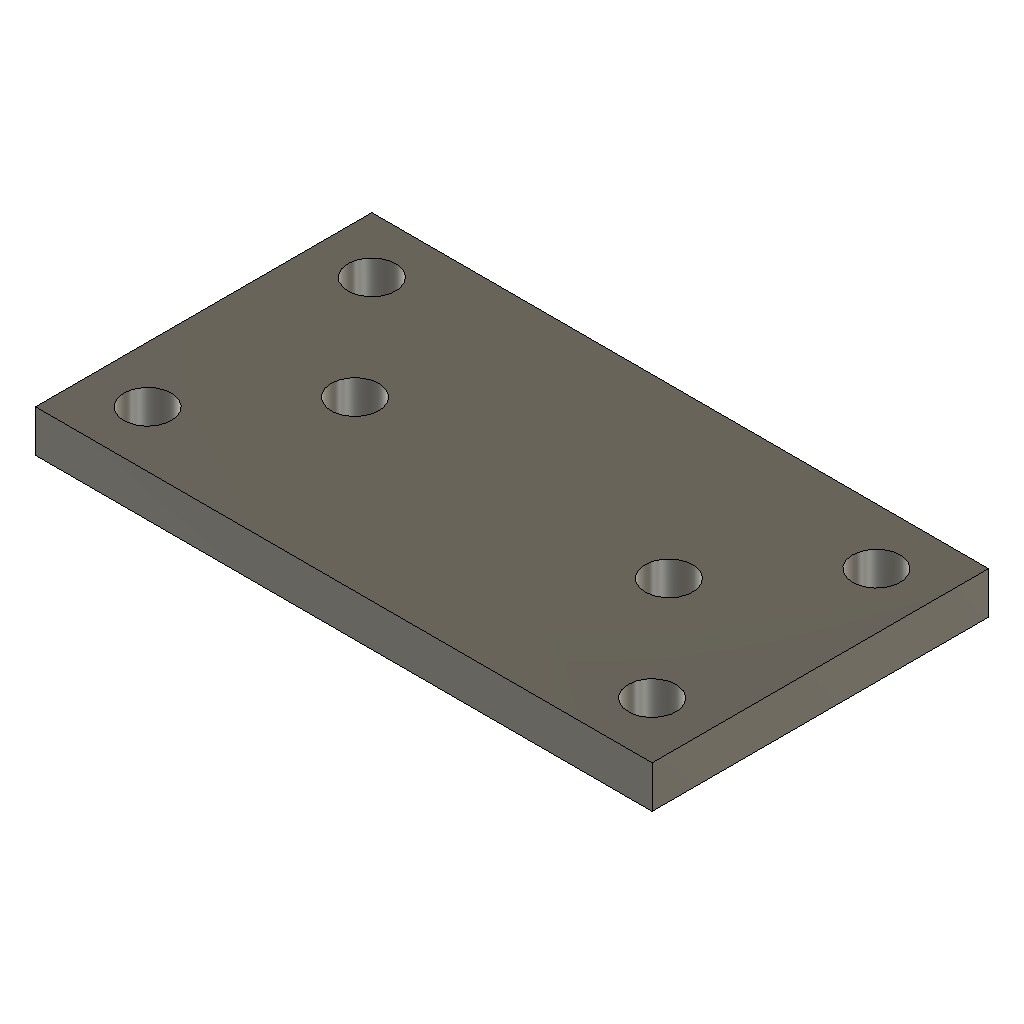
sg90_bracket_v1 (Autodesk Fusion 360 design; units mm, degrees)
part number: 2026-10-31-12-11-18-908
Autodesk Fusion 360 part; units mm, degrees
sketch "bracket_profile" plane through (0, 0, 0) normal (0, 0, 1) x (1, 0, 0)
  line L0 (-22, -12) -> (22, -12)
  line L1 (22, -12) -> (22, 12)
  line L2 (22, 12) -> (-22, 12)
  line L3 (-22, 12) -> (-22, -12)
  circle A0 centre (-11.2, 0) radius 1.7
  circle A1 centre (11.2, 0) radius 1.7
  circle A2 centre (-18, -8) radius 1.7
  circle A3 centre (-18, 8) radius 1.7
  circle A4 centre (18, -8) radius 1.7
  circle A5 centre (18, 8) radius 1.7
extrude "Extrude1" add sketch "bracket_profile" along normal blind 3
